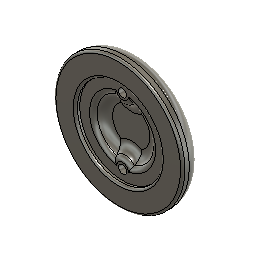
Flachenöffner (Autodesk Fusion 360 design; units mm, degrees)
Autodesk Fusion 360 part; units mm, degrees
sketch "Skizze1" plane through (0, 0, 0) normal (0, 0, 1) x (1, 0, 0)
  circle A0 centre (0, 0) radius 19.75
  circle A1 centre (0, 0) radius 15.25 construction
  line L0 (0, 19.75) -> (0, -19.75) construction
  circle A2 centre (0, 15.25) radius 1.925 construction
  circle A3 centre (0, -15.25) radius 1.925 construction
  circle A4 centre (0, 0) radius 13.5 construction
  circle A5 centre (0, 0) radius 29.75
  dimension "d1" = 39.5
  dimension "d2" = 30.5
  dimension "d3" = 3.85
  dimension "d4" = 3.85
  dimension "d5" = 27
  dimension "d6" = 10
  constraint coincident A0.centre A1.centre
  constraint concentric A0 A1
  constraint coincident A0 L0.start
  constraint coincident A0 L0.end
  constraint vertical L0
  constraint coincident L0 A2.centre
  constraint coincident A1 A2.centre
  constraint coincident L0 A3.centre
  constraint coincident A1 A3.centre
  constraint concentric A0 A4
  measures "d1" diameter of A0
  measures "d2" diameter of A1
  measures "d3" diameter of A2
  measures "d4" diameter of A3
  measures "d5" diameter of A4
extrude "Extrusion1" add sketch "Skizze1" along normal blind 6 contours A0
extrude "Extrusion2" add sketch "Skizze1" along normal blind 8
sketch "Skizze2" plane through (0, 0, 6) normal (0, 0, 1) x (1, 0, 0)
  circle A0 centre (0, 0) radius 19.75
  circle A1 centre (0, 0) radius 13.5
  point P0 (0, 15.25)
  point P1 (0, -15.25)
extrude "Extrusion3" cut sketch "Skizze2" against normal blind 4 contours A1
sketch "Skizze4" plane through (0, 0, 6) normal (0, 0, 1) x (1, 0, 0)
  circle A0 centre (0, 0) radius 13.5
  circle A1 centre (0, 0) radius 19.75
  circle A2 centre (0, -15.25) radius 4.5
  circle A3 centre (0, 15.25) radius 4.5
  point P0 (0, -15.25)
  point P1 (0, 15.25)
  constraint coincident P0 A2.centre
  constraint tangent A1 A2
  constraint coincident P1 A3.centre
  constraint tangent A1 A3
extrude "Extrusion5" add sketch "Skizze4" against normal blind 4 contours A0 A3 | A0 A2 picked at (-1.0855, 12.6007) picked at (-1.0855, -12.6007)
sketch "Skizze3" plane through (0, 0, 0) normal (0, 0, 1) x (1, 0, 0)
  circle A0 centre (0, -15.25) radius 1.85
  circle A1 centre (0, 15.25) radius 1.85
  point P0 (0, -15.25)
  point P1 (0, 15.25)
  dimension "d13" = 3.7
  dimension "d14" = 3.7
  constraint coincident P0 A0.centre
  constraint coincident P1 A1.centre
  measures "d13" diameter of A0
  measures "d14" diameter of A1
extrude "Extrusion4" cut sketch "Skizze3" along normal blind 6
fillet "Abrundung1" radius 5 4 edges at (0, -10.75, 2) (13.5, 0, 2) (-13.5, 0, 2) (0, 10.75, 2)
fillet "Abrundung2" radius 1 1 edges at (-27.7367, -10.7581, 8)
fillet "Abrundung3" radius 1 1 edges at (-18.4135, 7.1419, 8)
fillet "Abrundung4" radius 2.5 4 edges at (-13.5, 0, 6) (0, -10.75, 6) (13.5, 0, 6) (0, 10.75, 6)
sketch "Skizze5" plane through (0, 0, 0) normal (0, 0, -1) x (-1, 0, 0)
  circle A0 centre (0, -15.25) radius 1.85
  circle A1 centre (0, 15.25) radius 1.85
  circle A2 centre (0, 0) radius 29.75
extrude "Extrusion6" add sketch "Skizze5" along normal mid plane 2 contours A0 | A1 | A2
sketch "Skizze6" plane through (0, 0, -1) normal (0, 0, -1) x (-1, 0, 0)
  circle A0 centre (0, 0) radius 29.75
  spline S0 degree 3 poles (-3.0218, -20.4485) (-7.4772, -19.7661) (-11.3169, -17.8038) (-14.5643, -14.5498) knots 0 0 0 0 1 1 1 1
  spline S1 degree 3 poles (-14.5643, -14.5498) (-17.714, -11.3936) (-19.5414, -7.8387) (-20.3365, -3.321) knots 0 0 0 0 1 1 1 1
  spline S2 degree 3 poles (-20.3365, -3.321) (-20.5996, -1.8258) (-20.5768, -1.3756) (-20.2305, -1.2255) knots 0 0 0 0 1 1 1 1
  spline S3 degree 3 poles (-20.2305, -1.2255) (-19.5158, -0.9159) (-10.7382, 1.8155) (-10.6445, 1.7574) knots 0 0 0 0 1 1 1 1
  spline S4 degree 3 poles (-10.6445, 1.7574) (-10.5864, 1.7215) (-10.6801, 1.2493) (-10.8526, 0.7081) knots 0 0 0 0 1 1 1 1
  spline S5 degree 3 poles (-10.8526, 0.7081) (-11.1016, -0.0732) (-11.1574, -0.4783) (-11.1234, -1.2577) knots 0 0 0 0 1 1 1 1
  spline S6 degree 3 poles (-11.1234, -1.2577) (-11.0836, -2.1695) (-11.0513, -2.2688) (-10.6699, -2.6509) knots 0 0 0 0 1 1 1 1
  spline S7 degree 3 poles (-10.6699, -2.6509) (-10.2934, -3.0282) (-10.1811, -3.0663) (-9.3186, -3.11) knots 0 0 0 0 1 1 1 1
  spline S8 degree 3 poles (-9.3186, -3.11) (-8.5243, -3.1502) (-8.2731, -3.1087) (-7.7042, -2.8464) knots 0 0 0 0 1 1 1 1
  spline S9 degree 3 poles (-7.7042, -2.8464) (-7.3336, -2.6752) (-6.7759, -2.3209) (-6.4649, -2.0588) knots 0 0 0 0 1 1 1 1
  spline S10 degree 3 poles (-6.4649, -2.0588) (-6.1394, -1.7846) (-5.8789, -1.6442) (-5.851, -1.728) knots 0 0 0 0 1 1 1 1
  spline S11 degree 3 poles (-5.851, -1.728) (-5.8244, -1.8081) (-5.9056, -2.2563) (-6.0314, -2.7242) knots 0 0 0 0 1 1 1 1
  spline S12 degree 3 poles (-6.0314, -2.7242) (-6.2374, -3.4898) (-6.362, -3.6825) (-7.2785, -4.6533) knots 0 0 0 0 1 1 1 1
  spline S13 degree 3 poles (-7.2785, -4.6533) (-9.8134, -7.3382) (-11.1462, -9.668) (-11.1451, -11.4124) knots 0 0 0 0 1 1 1 1
  spline S14 degree 3 poles (-11.1451, -11.4124) (-11.1443, -12.7347) (-10.4421, -13.4263) (-9.2907, -13.2391) knots 0 0 0 0 1 1 1 1
  spline S15 degree 3 poles (-9.2907, -13.2391) (-7.7354, -12.9861) (-6.902, -11.5056) (-5.8214, -7.076) knots 0 0 0 0 1 1 1 1
  line L0 (-5.8214, -7.076) -> (-5.1841, -4.4629)
  line L1 (-5.1841, -4.4629) -> (-4.3749, -3.6914)
  spline S16 degree 3 poles (-4.3749, -3.6914) (-3.0833, -2.46) (-1.7739, -1.4315) (-1.6577, -1.5572) knots 0 0 0 0 1 1 1 1
  spline S17 degree 3 poles (-1.6577, -1.5572) (-1.5994, -1.6201) (-1.7461, -2.3282) (-1.9837, -3.1307) knots 0 0 0 0 1 1 1 1
  spline S18 degree 3 poles (-1.9837, -3.1307) (-3.0958, -6.8879) (-3.1947, -8.9941) (-2.2726, -9.2873) knots 0 0 0 0 1 1 1 1
  spline S19 degree 3 poles (-2.2726, -9.2873) (-1.1093, -9.6573) (0.2618, -7.9864) (1.0835, -5.1973) knots 0 0 0 0 1 1 1 1
  spline S20 degree 3 poles (1.0835, -5.1973) (1.5162, -3.7286) (1.6255, -1.7255) (1.3277, -0.7201) knots 0 0 0 0 1 1 1 1
  spline S21 degree 3 poles (1.3277, -0.7201) (0.9702, 0.4865) (0.9387, 0.432) (2.1478, 0.6951) knots 0 0 0 0 1 1 1 1
  spline S22 degree 3 poles (2.1478, 0.6951) (2.7387, 0.8237) (3.4974, 1.0205) (3.8337, 1.1324) knots 0 0 0 0 1 1 1 1
  spline S23 degree 3 poles (3.8337, 1.1324) (4.1699, 1.2443) (4.4778, 1.3031) (4.5178, 1.263) knots 0 0 0 0 1 1 1 1
  spline S24 degree 3 poles (4.5178, 1.263) (4.5578, 1.2229) (4.4971, 0.8564) (4.383, 0.4487) knots 0 0 0 0 1 1 1 1
  spline S25 degree 3 poles (4.383, 0.4487) (3.9509, -1.0944) (4.192, -2.2674) (5.0617, -2.8532) knots 0 0 0 0 1 1 1 1
  spline S26 degree 3 poles (5.0617, -2.8532) (5.4533, -3.117) (5.6229, -3.1467) (6.5178, -3.1082) knots 0 0 0 0 1 1 1 1
  spline S27 degree 3 poles (6.5178, -3.1082) (7.738, -3.0558) (8.4306, -2.7553) (9.4208, -1.8484) knots 0 0 0 0 1 1 1 1
  spline S28 degree 3 poles (9.4208, -1.8484) (9.7936, -1.5069) (10.1312, -1.2276) (10.171, -1.2276) knots 0 0 0 0 1 1 1 1
  spline S29 degree 3 poles (10.171, -1.2276) (10.2108, -1.2276) (10.3059, -1.4605) (10.3825, -1.7453) knots 0 0 0 0 1 1 1 1
  spline S30 degree 3 poles (10.3825, -1.7453) (10.459, -2.03) (10.7103, -2.4693) (10.941, -2.7216) knots 0 0 0 0 1 1 1 1
  spline S31 degree 3 poles (10.941, -2.7216) (11.325, -3.1415) (11.4283, -3.184) (12.1679, -3.2268) knots 0 0 0 0 1 1 1 1
  spline S32 degree 3 poles (12.1679, -3.2268) (13.0679, -3.2788) (14.5907, -2.9042) (18.3271, -1.7115) knots 0 0 0 0 1 1 1 1
  spline S33 degree 3 poles (18.3271, -1.7115) (19.5777, -1.3123) (20.4294, -1.1006) (20.4951, -1.1726) knots 0 0 0 0 1 1 1 1
  spline S34 degree 3 poles (20.4951, -1.1726) (20.6515, -1.3437) (20.4235, -3.2357) (20.0644, -4.7456) knots 0 0 0 0 1 1 1 1
  spline S35 degree 3 poles (20.0644, -4.7456) (19.1467, -8.6046) (17.419, -11.6848) (14.561, -14.5575) knots 0 0 0 0 1 1 1 1
  spline S36 degree 3 poles (14.561, -14.5575) (11.5836, -17.5501) (8.2272, -19.3767) (4.0712, -20.2664) knots 0 0 0 0 1 1 1 1
  spline S37 degree 3 poles (4.0712, -20.2664) (2.4439, -20.6148) (-1.3079, -20.7111) (-3.0218, -20.4485) knots 0 0 0 0 1 1 1 1
  spline S38 degree 3 poles (-9.8357, -11.6895) (-10.0651, -11.0904) (-9.2179, -9.1374) (-8.0803, -7.6426) knots 0 0 0 0 1 1 1 1
  spline S39 degree 3 poles (-8.0803, -7.6426) (-6.9523, -6.1606) (-6.8819, -6.3344) (-7.6219, -8.7748) knots 0 0 0 0 1 1 1 1
  spline S40 degree 3 poles (-7.6219, -8.7748) (-8.0396, -10.1526) (-8.4927, -11.1522) (-8.9025, -11.5999) knots 0 0 0 0 1 1 1 1
  spline S41 degree 3 poles (-8.9025, -11.5999) (-9.2026, -11.9277) (-9.7252, -11.9779) (-9.8357, -11.6895) knots 0 0 0 0 1 1 1 1
  spline S42 degree 3 poles (-1.549, -7.3758) (-1.7102, -7.2143) (-0.4495, -2.1137) (-0.1224, -1.6038) knots 0 0 0 0 1 1 1 1
  spline S43 degree 3 poles (-0.1224, -1.6038) (-0.0179, -1.441) (0.0125, -1.4416) (0.1216, -1.6082) knots 0 0 0 0 1 1 1 1
  spline S44 degree 3 poles (0.1216, -1.6082) (0.5159, -2.2101) (-0.0428, -4.9789) (-0.909, -6.715) knots 0 0 0 0 1 1 1 1
  spline S45 degree 3 poles (-0.909, -6.715) (-1.2512, -7.4011) (-1.3854, -7.5396) (-1.549, -7.3758) knots 0 0 0 0 1 1 1 1
  spline S46 degree 3 poles (11.8268, -1.725) (11.4757, -1.3363) (11.5248, 0.0287) (11.9508, 1.7256) knots 0 0 0 0 1 1 1 1
  spline S47 degree 3 poles (11.9508, 1.7256) (12.3238, 3.2112) (12.3013, 3.5515) (11.8223, 3.672) knots 0 0 0 0 1 1 1 1
  spline S48 degree 3 poles (11.8223, 3.672) (11.3885, 3.7811) (11.0954, 3.4786) (10.7571, 2.5722) knots 0 0 0 0 1 1 1 1
  spline S49 degree 3 poles (10.7571, 2.5722) (9.8343, 0.0996) (7.8964, -1.8572) (6.3667, -1.8607) knots 0 0 0 0 1 1 1 1
  spline S50 degree 3 poles (6.3667, -1.8607) (5.7584, -1.8621) (5.4416, -1.5455) (5.4416, -0.9362) knots 0 0 0 0 1 1 1 1
  spline S51 degree 3 poles (5.4416, -0.9362) (5.4416, -0.4644) (5.9756, 1.1205) (6.4555, 2.0731) knots 0 0 0 0 1 1 1 1
  spline S52 degree 3 poles (6.4555, 2.0731) (6.9289, 3.0129) (6.9448, 3.422) (6.5157, 3.6179) knots 0 0 0 0 1 1 1 1
  spline S53 degree 3 poles (6.5157, 3.6179) (6.2355, 3.7458) (6.0634, 3.693) (5.0912, 3.1813) knots 0 0 0 0 1 1 1 1
  spline S54 degree 3 poles (5.0912, 3.1813) (3.8187, 2.5114) (2.4159, 2.0073) (2.2598, 2.1638) knots 0 0 0 0 1 1 1 1
  spline S55 degree 3 poles (2.2598, 2.1638) (2.2009, 2.2228) (2.5261, 2.7827) (2.9824, 3.4082) knots 0 0 0 0 1 1 1 1
  spline S56 degree 3 poles (2.9824, 3.4082) (4.5782, 5.5953) (6.0713, 8.2783) (6.6439, 9.9877) knots 0 0 0 0 1 1 1 1
  spline S57 degree 3 poles (6.6439, 9.9877) (7.1603, 11.5289) (7.0384, 12.416) (6.2596, 12.7864) knots 0 0 0 0 1 1 1 1
  spline S58 degree 3 poles (6.2596, 12.7864) (5.4353, 13.1783) (4.7589, 12.9441) (3.8772, 11.9614) knots 0 0 0 0 1 1 1 1
  spline S59 degree 3 poles (3.8772, 11.9614) (3.0482, 11.0375) (2.2499, 9.327) (0.9492, 5.6873) knots 0 0 0 0 1 1 1 1
  spline S60 degree 3 poles (0.9492, 5.6873) (0.3507, 4.0125) (-0.2021, 2.4822) (-0.2792, 2.2865) knots 0 0 0 0 1 1 1 1
  spline S61 degree 3 poles (-0.2792, 2.2865) (-0.4143, 1.9434) (-0.4428, 1.9337) (-1.0765, 2.013) knots 0 0 0 0 1 1 1 1
  spline S62 degree 3 poles (-1.0765, 2.013) (-1.5981, 2.0783) (-1.7772, 2.0517) (-1.9447, 1.8839) knots 0 0 0 0 1 1 1 1
  spline S63 degree 3 poles (-1.9447, 1.8839) (-2.262, 1.5658) (-2.2002, 1.2365) (-1.758, 0.8897) knots 0 0 0 0 1 1 1 1
  line L2 (-1.758, 0.8897) -> (-1.3604, 0.5779)
  line L3 (-1.3604, 0.5779) -> (-1.6631, 0.3237)
  spline S64 degree 3 poles (-1.6631, 0.3237) (-2.7432, -0.5838) (-4.0804, -1.6082) (-4.1847, -1.6082) knots 0 0 0 0 1 1 1 1
  spline S65 degree 3 poles (-4.1847, -1.6082) (-4.3606, -1.6082) (-4.3664, -1.6375) (-3.723, 0.7631) knots 0 0 0 0 1 1 1 1
  spline S66 degree 3 poles (-3.723, 0.7631) (-3.0917, 3.1184) (-3.0763, 3.5339) (-3.6153, 3.6695) knots 0 0 0 0 1 1 1 1
  spline S67 degree 3 poles (-3.6153, 3.6695) (-4.0617, 3.7818) (-4.2304, 3.5963) (-4.9425, 2.2108) knots 0 0 0 0 1 1 1 1
  spline S68 degree 3 poles (-4.9425, 2.2108) (-6.1659, -0.1695) (-7.657, -1.6869) (-8.9121, -1.8286) knots 0 0 0 0 1 1 1 1
  spline S69 degree 3 poles (-8.9121, -1.8286) (-9.2852, -1.8708) (-9.5667, -1.8372) (-9.6884, -1.7359) knots 0 0 0 0 1 1 1 1
  spline S70 degree 3 poles (-9.6884, -1.7359) (-10.1224, -1.3751) (-9.759, 0.2879) (-8.8506, 2.0994) knots 0 0 0 0 1 1 1 1
  spline S71 degree 3 poles (-8.8506, 2.0994) (-8.3997, 2.9986) (-8.381, 3.4242) (-8.7844, 3.6084) knots 0 0 0 0 1 1 1 1
  spline S72 degree 3 poles (-8.7844, 3.6084) (-9.0345, 3.7225) (-9.9251, 3.4758) (-14.324, 2.074) knots 0 0 0 0 1 1 1 1
  spline S73 degree 3 poles (-14.324, 2.074) (-17.207, 1.1553) (-19.7562, 0.3445) (-19.9889, 0.2722) knots 0 0 0 0 1 1 1 1
  spline S74 degree 3 poles (-19.9889, 0.2722) (-20.6388, 0.0703) (-20.681, 0.1966) (-20.5178, 1.8568) knots 0 0 0 0 1 1 1 1
  spline S75 degree 3 poles (-20.5178, 1.8568) (-20.0053, 7.0704) (-17.951, 11.3059) (-14.1673, 14.9494) knots 0 0 0 0 1 1 1 1
  spline S76 degree 3 poles (-14.1673, 14.9494) (-11.1045, 17.8988) (-7.4829, 19.7062) (-3.2319, 20.4067) knots 0 0 0 0 1 1 1 1
  spline S77 degree 3 poles (-3.2319, 20.4067) (-1.5468, 20.6844) (1.7704, 20.6561) (3.5641, 20.3488) knots 0 0 0 0 1 1 1 1
  spline S78 degree 3 poles (3.5641, 20.3488) (12.0648, 18.8926) (18.9167, 12.0099) (20.3072, 3.5304) knots 0 0 0 0 1 1 1 1
  spline S79 degree 3 poles (20.3072, 3.5304) (20.6216, 1.6126) (20.6803, 0.6163) (20.4881, 0.4598) knots 0 0 0 0 1 1 1 1
  spline S80 degree 3 poles (20.4881, 0.4598) (20.0815, 0.129) (13.0297, -1.9874) (12.3303, -1.9884) knots 0 0 0 0 1 1 1 1
  spline S81 degree 3 poles (12.3303, -1.9884) (12.1844, -1.9884) (11.9579, -1.8701) (11.8268, -1.725) knots 0 0 0 0 1 1 1 1
  spline S82 degree 3 poles (2.0882, 4.8943) (2.2542, 5.4695) (3.3122, 8.3092) (3.6244, 9.0179) knots 0 0 0 0 1 1 1 1
  spline S83 degree 3 poles (3.6244, 9.0179) (4.0341, 9.9473) (4.9998, 11.4093) (5.2738, 11.5147) knots 0 0 0 0 1 1 1 1
  spline S84 degree 3 poles (5.2738, 11.5147) (5.3894, 11.5591) (5.5382, 11.5411) (5.6044, 11.4747) knots 0 0 0 0 1 1 1 1
  spline S85 degree 3 poles (5.6044, 11.4747) (5.9142, 11.1643) (4.4882, 8.0348) (3.0309, 5.8267) knots 0 0 0 0 1 1 1 1
  spline S86 degree 3 poles (3.0309, 5.8267) (2.2471, 4.639) (1.9216, 4.317) (2.0882, 4.8943) knots 0 0 0 0 1 1 1 1
extrude "Extrusion7" cut sketch "Skizze6" against normal blind 0.5 contours S0 S1 S2 S3 S4 S5 S6 S7 S8 S9 S10 S11 S12 S13 S14 S15 L0 L1 S16 S17 S18 S19 S20 S21 S22 S23 S24 S25 S26 S27 S28 S29 S30 S31 S32 S33 S34 S35 S36 S37 | S38 S39 S40 S41 | S42 S43 S44 S45 | S46 S47 S48 S49 S50 S51 S52 S53 S54 S55 S56 S57 S58 S59 S60 S61 S62 S63 L2 L3 S64 S65 S66 S67 S68 S69 S70 S71 S72 S73 S74 S75 S76 S77 S78 S79 S80 S81 | S82 S83 S84 S85 S86
fillet "Abrundung5" radius 6 1 edges at (27.7367, -10.7581, -1)
fillet "Abrundung6" radius 1 1 edges at (-1.7248, 15.919, 1)
fillet "Abrundung7" radius 1 1 edges at (-1.7248, -14.581, 1)
named bodies: "Flaschenöffner"
